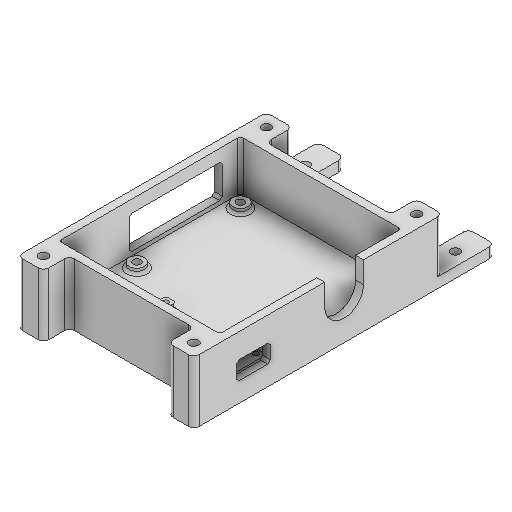
# Autodesk Inventor part: 3DP_PLA_Electronics_Box_Bottom_REVB
Saved by Autodesk Inventor 2027 (Build 310192060, 192F)
## iProperties
Created: 2026-03-08
Part Number: 3DP_PLA_Electronics_Box_Bottom_REVB
Material: Generic
Document SubType Name: Modeling
Designer: User
Density: 1 g/cm^3
Appearance: Default
Author: User
Autodesk Inventor part; units mm, degrees
ref_plane "YZ Plane" through (0, 0, 0) normal (1, 0, 0) x (0, 1, 0)
ref_plane "XZ Plane" through (0, 0, 0) normal (0, 1, 0) x (-1, 0, 0)
ref_plane "XY Plane" through (0, 0, 0) normal (0, 0, 1) x (1, 0, 0)
sketch "Sketch1" plane through (0, 0, 0) normal (0, 1, 0) x (-1, 0, 0)
  line L0 (30, 24) -> (-30, 24)
  line L1 (-30, 24) -> (-30, -24)
  line L2 (-30, -24) -> (30, -24)
  line L3 (30, -24) -> (30, 24)
  line L4 (31, 25) -> (-31, 25)
  line L5 (-31, 25) -> (-31, -25)
  line L6 (-31, -25) -> (31, -25)
  line L7 (31, -25) -> (31, 25)
  line L8 (31, 25) -> (31, 45)
  line L9 (31, 45) -> (-31, 45)
  line L10 (-31, 45) -> (-31, 25)
  line L11 (15, 26.9) -> (15, 43.1)
  line L12 (15, 43.1) -> (-30, 43.1)
  line L13 (-30, 43.1) -> (-30, 26.9)
  line L14 (-30, 26.9) -> (15, 26.9)
  line L15 (8, 43.1) -> (8, 26.9)
  line L16 (4, 43.1) -> (4, 26.9)
  line L17 (-26.7, 26.9) -> (-26.7, 43.1)
  circle A0 centre (-26, 20) radius 3
  circle A1 centre (26, 20) radius 3
  circle A2 centre (-26, -20) radius 3
  circle A3 centre (26, -20) radius 3
  line L18 (-30, 43.1) -> (-31, 43.1)
  line L19 (-30, 26.9) -> (-31, 26.9)
  point P0 (0, 0)
  point P1 (-7.5, 35)
  point P2 (-28.7, 28.7)
  point P3 (6, 28.7)
  point P4 (6, 41.3)
  point P5 (-28.7, 41.3)
  dimension "d0" = 60
  dimension "d1" = 48
  dimension "d2" = 30
  dimension "d3" = 24
  dimension "d4" = 1
  dimension "d5" = 20
  dimension "d6" = 4
  dimension "d7" = 4
  dimension "d8" = 4
  dimension "d9" = 4
  dimension "d10" = 45
  dimension "d11" = 16.2
  dimension "d12" = 8.1
  dimension "d13" = 22.5
  dimension "d14" = 12.6
  dimension "d15" = 1.8
  dimension "d16" = 9
  dimension "d17" = 43.7
  dimension "d18" = 1
  dimension "d19" = 1.9
  dimension "d43" = 2
  dimension "d45" = 2
  dimension "d46" = 2
  dimension "d50" = 6
  dimension "d51" = 6
  dimension "d52" = 6
  dimension "d53" = 6
  constraints: 40 end point, 10 perpendicular, 8 point on line, 6 parallel, 4 centre point, 4 coincident, 4 horizontal alignment, 4 vertical alignment, 2 horizontal, 1 vertical, 3 other
  measures "d0" distance of L0.start L0.end
  measures "d1" distance of L0.end L1.end
  measures "d2" distance from line of L3 point (0, 0)
  measures "d3" distance from line of L0 point (0, 0)
  measures "d4" distance between parallel lines of L3 L7
  measures "d5" distance of L9.end L4.end
  measures "d6" distance from line of L0 point (26, 20)
  measures "d7" distance from line of L3 point (26, 20)
  measures "d8" distance from line of L1 point (-26, 20)
  measures "d9" distance from line of L2 point (-26, -20)
  measures "d10" distance of L13.end L11.start
  measures "d11" distance of L11.start L11.end
  measures "d12" distance from line of point (-7.5, 35) L14
  measures "d13" distance from line of L11 point (-7.5, 35)
  measures "d14" distance of point (-28.7, 41.3) point (-28.7, 28.7)
  measures "d15" distance from line of L14 point (-28.7, 28.7)
  measures "d16" distance from line of point (6, 41.3) L11
  measures "d17" distance from line of point (-28.7, 41.3) L11
  measures "d18" distance between parallel lines of L10 L13
  measures "d19" distance between parallel lines of L12 L9
  measures "d43" distance from line of point (-28.7, 41.3) L17
  measures "d45" distance from line of point (6, 41.3) L16
  measures "d46" distance from line of L15 point (6, 41.3)
  measures "d50" diameter of A0
  measures "d51" diameter of A1
  measures "d52" diameter of A2
  measures "d53" diameter of A3
extrude "Extrusion1" add sketch "Sketch1" against normal blind 5 contours L3 L2 L1 L0 | L7 L6 L5 L4 | L4 L10 L19 L14 L11 L12 L18 L9 L8 | L10 L18 L13 L19 | L13 L12 L17 L14 | L17 L12 L16 L14 | L16 L12 L15 L14 | L15 L12 L11 L14 | A0 | A1 | A2 | A3
extrude "Extrusion4" add sketch "Sketch1" along normal blind 3 contours L10 L18 L13 L19 | L13 L12 L17 L14 | L16 L12 L15 L14
hole "Hole2" at (28.7, 0, 41.3) at (-6, 0, 41.3) at (-6, 0, 28.7) at (28.7, 0, 28.7) direction (0, -1, 0) diameter 2 end through all both
extrude "Extrusion5" add sketch "Sketch1" along normal blind 2 contours A0 | A1 | A2 | A3
hole "Hole1" at (-26, 0, 20) at (26, 0, 20) at (26, 0, -20) at (-26, 0, -20) direction (0, 1, 0) diameter 3 end through all both
sketch "Sketch2" plane through (0, 0, 0) normal (0, 1, 0) x (1, 0, 0)
  line L0 (-31, -45) -> (31, -45) projected
  line L1 (31, -45) -> (31, -43.1) projected
  line L2 (31, 25) -> (-31, 25) projected
  line L3 (-31, 25) -> (-31, -45) projected
  line L4 (-34, -48) -> (34, -48)
  line L5 (34, -48) -> (34, 28)
  line L6 (34, 28) -> (-34, 28)
  line L7 (-34, 28) -> (-34, -48)
  line L8 (31, -43.1) -> (26.7, -43.1) projected
  line L9 (26.7, -43.1) -> (26.7, -26.9) projected
  line L10 (26.7, -26.9) -> (31, -26.9) projected
  line L11 (31, -26.9) -> (31, 25) projected
  line L12 (31, -43.1) -> (31, -26.9) projected
  point P0 (0, 0)
  dimension "d36" = 3
  constraints: 8 end point, 3 other
  measures "d36" distance between parallel lines of L3 L7
extrude "Extrusion2" add sketch "Sketch2" against normal blind 5
extrude "Extrusion3" add sketch "Sketch2" along normal blind 19
fillet "Fillet1" radius 1 4 edges at (31, 9.5, 45) (31, 9.5, -25) (-31, 9.5, -25) (-31, 9.5, 45)
fillet "Fillet3" radius 1 17 edges at (-4, 0, 35) (-6, 0, 26.9) (-8, 0, 35) (-6, 0, 43.1) (26.7, 0, 35) (26.7, 1.5, 26.9) (26.7, 1.5, 43.1) (-4, 1.5, 26.9) (-8, 1.5, 26.9) (-8, 1.5, 43.1) (-4, 1.5, 43.1) (-23, 0, 20) (29, 0, 20) (29, 0, -20) (-23, 0, -20) (28.85, 0, 26.9) (28.85, 0, 43.1)
sketch "Sketch3" plane through (34, -5, 48) normal (1, 0, 0) x (0, 0, -1)
  line L0 (0, 24) -> (0, 0) projected
  line L1 (76, 0) -> (0, 0) projected
  arc A0 (40.5, 15.68) -> (55.5, 15.68) centre (48, 15.68) ccw
  line L2 (40.5, 15.68) -> (40.5, 24)
  line L3 (73, 24) -> (3, 24) projected
  line L4 (55.5, 15.68) -> (55.5, 24)
  line L5 (76, 0) -> (76, 24) projected
  line L6 (0, 24) -> (76, 24) projected
  point P0 (48, 5)
  point P1 (72, 24)
  point P2 (4, 24)
  point P3 (4.9, 24)
  dimension "d56" = 15
  dimension "d57" = 15.68
  constraints: 4 end point, 2 point on circle, 2 point on line, 1 centre point, 1 tangent, 1 vertical
  measures "d56" diameter of A0
  measures "d57" distance from line of L1 A0.centre
extrude "Extrusion6" cut sketch "Sketch3" against normal blind 18 contours L3 L4 A0 L2
sketch "Sketch4" plane through (-34, -5, -28) normal (-1, 0, 0) x (0, 0, 1)
  line L0 (76, 0) -> (0, 0) projected
  line L1 (12, 17.25) -> (44, 17.25)
  line L2 (44, 17.25) -> (44, 8.5)
  line L3 (44, 8.5) -> (12, 8.5)
  line L4 (12, 8.5) -> (12, 17.25)
  line L5 (10, 6.5) -> (46, 6.5)
  line L6 (46, 6.5) -> (46, 19.25)
  line L7 (46, 19.25) -> (10, 19.25)
  line L8 (10, 19.25) -> (10, 6.5)
  line L9 (0, 0) -> (0, 24) projected
  line L10 (76, 0) -> (76, 24) projected
  line L11 (0, 24) -> (76, 24) projected
  point P0 (28, 5)
  dimension "d61" = 8.5
  dimension "d63" = 8.75
  dimension "d65" = 2
  constraints: 16 end point, 4 parallel, 2 perpendicular, 1 horizontal, 3 other
  measures "d61" distance between parallel lines of L0 L3
  measures "d63" distance of L1.end L2.end
  measures "d65" distance between parallel lines of L3 L5
extrude "Extrusion7" cut sketch "Sketch4" against normal blind 3 contours L1 L2 L3 L4 | L8 L7 L6 L5
chamfer "Chamfer1" distance 1 angle 45 4 edges at (-32.5, 14.25, 18) (-32.5, 1.5, 18) (-32.5, 1.5, -18) (-32.5, 14.25, -18)
sketch "Sketch5" plane through (34, -5, 48) normal (1, 0, 0) x (0, 0, -1)
  line L0 (8.5, 12.6) -> (17.5, 12.6)
  line L1 (17.5, 12.6) -> (17.5, 9.6)
  line L2 (17.5, 9.6) -> (8.5, 9.6)
  line L3 (8.5, 9.6) -> (8.5, 12.6)
  line L4 (0, 24) -> (0, 0) projected
  line L5 (76, 0) -> (0, 0) projected
  line L6 (6.5, 7.6) -> (19.5, 7.6)
  line L7 (19.5, 7.6) -> (19.5, 14.6)
  line L8 (19.5, 14.6) -> (6.5, 14.6)
  line L9 (6.5, 14.6) -> (6.5, 7.6)
  point P0 (48, 5)
  point P1 (0, 5)
  dimension "d71" = 3
  dimension "d72" = 9
  dimension "d73" = 8.5
  dimension "d74" = 9.6
  dimension "d75" = 2
  constraints: 16 end point, 4 parallel, 2 perpendicular, 1 horizontal, 3 other
  measures "d71" distance of L0.end L1.end
  measures "d72" distance of L1.end L2.end
  measures "d73" distance between parallel lines of L4 L3
  measures "d74" distance between parallel lines of L5 L2
  measures "d75" distance between parallel lines of L2 L6
extrude "Extrusion8" cut sketch "Sketch5" against normal blind 3 contours L0 L1 L2 L3 | L9 L8 L7 L6
chamfer "Chamfer2" distance 1 angle 45 4 edges at (32.5, 2.6, 41.5) (32.5, 2.6, 28.5) (32.5, 9.6, 28.5) (32.5, 9.6, 41.5)
chamfer "Chamfer3" distance 0.4 angle 45 1 edges at (31, 2.6, 35)
sketch "Sketch6" plane through (0, -5, 0) normal (0, -1, 0) x (1, 0, 0)
  line L0 (-34, -28) -> (34, -28) projected
  line L1 (34, -28) -> (34, 48) projected
  line L2 (-34, 48) -> (-34, -28) projected
  line L3 (34, 48) -> (-34, 48) projected
  line L4 (34, -28) -> (34, -38)
  line L5 (34, -38) -> (24, -38)
  line L6 (24, -38) -> (24, -28)
  line L7 (-24, -28) -> (-24, -38)
  line L8 (-24, -38) -> (-34, -38)
  line L9 (-34, -38) -> (-34, -28)
  line L10 (34, 48) -> (34, 58)
  line L11 (34, 58) -> (24, 58)
  line L12 (24, 58) -> (24, 48)
  line L13 (-34, 48) -> (-34, 58)
  line L14 (-34, 58) -> (-24, 58)
  line L15 (-24, 58) -> (-24, 48)
  line L16 (34, -38) -> (34, -58)
  line L17 (34, -58) -> (24, -58)
  line L18 (24, -58) -> (24, -38)
  line L19 (-24, -38) -> (-24, -58)
  line L20 (-24, -58) -> (-34, -58)
  line L21 (-34, -58) -> (-34, -38)
  point P0 (0, 0)
  point P1 (29, -33)
  point P2 (-29, -33)
  point P3 (-29, 53)
  point P4 (29, 53)
  point P5 (29, -48)
  point P6 (-29, -48)
  dimension "d84" = 10
  dimension "d85" = 10
  dimension "d86" = 10
  dimension "d87" = 10
  dimension "d88" = 10
  dimension "d89" = 10
  dimension "d90" = 10
  dimension "d91" = 5
  dimension "d92" = 5
  dimension "d93" = 5
  dimension "d94" = 5
  dimension "d95" = 5
  dimension "d97" = 5
  dimension "d98" = 5
  dimension "d99" = 5
  dimension "d110" = 20
  dimension "d111" = 5
  dimension "d112" = 5
  dimension "d113" = 10
  dimension "d114" = 10
  constraints: 36 end point, 12 point on line, 9 perpendicular, 2 parallel, 2 vertical
  measures "d84" distance of L0.end L4.end
  measures "d85" distance of L4.end L5.end
  measures "d86" distance of L7.end L8.end
  measures "d87" distance between parallel lines of L0 L8
  measures "d88" distance of L10.end L11.end
  measures "d89" distance of L13.end L14.end
  measures "d90" distance of L1.end L10.end
  measures "d91" distance from line of L5 point (29, -33)
  measures "d92" distance from line of L4 point (29, -33)
  measures "d93" distance from line of L7 point (-29, -33)
  measures "d94" distance from line of L8 point (-29, -33)
  measures "d95" distance from line of L10 point (29, 53)
  measures "d97" distance from line of L14 point (-29, 53)
  measures "d98" distance from line of L15 point (-29, 53)
  measures "d99" distance from line of point (29, 53) L11
  measures "d110" distance of L4.end L16.end
  measures "d111" distance from line of L16 point (29, -48)
  measures "d112" distance from line of L19 point (-29, -48)
  measures "d113" distance from line of L5 point (29, -48)
  measures "d114" distance from line of L8 point (-29, -48)
extrude "Extrusion9" add sketch "Sketch6" against normal up to surface (24 mm away) contours L0 L7 L8 L9 | L13 L14 L15 L3 | L0 L4 L5 L6 | L12 L11 L10 L3
hole "Hole3" at (29, -5, -33) at (-29, -5, -33) at (-29, -5, 53) at (29, -5, 53) direction (0, 1, 0) diameter 3.5 end through all
extrude "Extrusion10" add sketch "Sketch6" against normal blind 4 contours L8 L19 L20 L21 | L5 L16 L17 L18
hole "Hole4" at (29, -5, -48) at (-29, -5, -48) direction (0, 1, 0) diameter 3.5 end through all
fillet "Fillet5" radius 2 16 edges at (34, 9, -38) (24, 9, -38) (24, 7, -28) (24, -3, -58) (34, -3, -58) (-24, -3, -58) (-34, -3, -58) (-34, 9, -38) (-24, 9, -38) (-24, 7, -28) (34, 7, 58) (24, 7, 58) (24, 7, 48) (-24, 7, 48) (-24, 7, 58) (-34, 7, 58)
equation "\"d2\" = 0.5 * d0"
equation "\"d3\" = 0.5 * d1"
equation "\"d8\" = d6"
equation "\"d9\" = d6"
equation "\"d12\" = 0.5 * d11"
equation "\"d13\" = 0.5 * d10"
equation "\"d15\" = -0.5 * d14 + 0.5 * d11"
equation "\"d19\" = -0.5 * d11 + 0.5 * d5"
equation "\"d45\" = d46"
body "Solid1"
